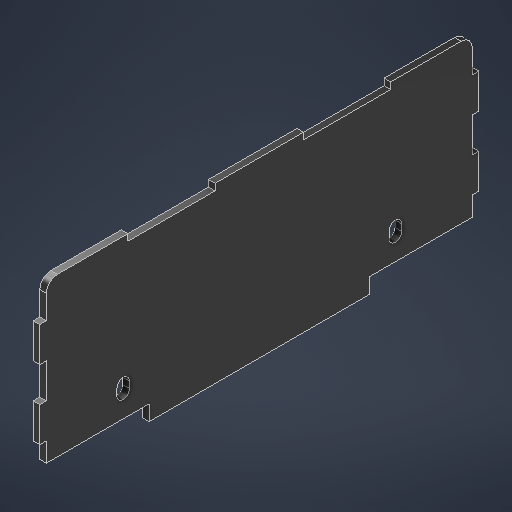
# Autodesk Inventor part: ControlBoxWidthFace
Saved by Autodesk Inventor 2027.1 (Build 311270010, 270A)
## iProperties
Created: 2026-10-13
Part Number: ControlBoxWidthFace
Material: MDF Medium Density Fiberboard
Document SubType Name: Modeling
Designer: SDS Scholar
Density: 0.8 g/cm^3
Appearance: Glossy - Black
Mass: 36.6564 g
Surface Area: 323.47 cm^2
Volume: 45.8205 cm^3
Author: SDS Scholar
Autodesk Inventor part; units mm, degrees
ref_plane "YZ Plane" through (0, 0, 0) normal (1, 0, 0) x (0, 1, 0)
ref_plane "XZ Plane" through (0, 0, 0) normal (0, 1, 0) x (-1, 0, 0)
ref_plane "XY Plane" through (0, 0, 0) normal (0, 0, 1) x (1, 0, 0)
sketch "Sketch1" plane through (0, 0, 0) normal (1, 0, 0) x (0, 1, 0)
  line L0 (39.5, 100) -> (-39.5, 100)
  line L1 (-39.5, 100) -> (-39.5, -100)
  line L2 (-39.5, -100) -> (39.5, -100)
  line L3 (39.5, -100) -> (39.5, 100)
  point P0 (0, 0)
  point P1 (39.5, 0)
  point P2 (0, -100)
  dimension "d0" = 200
  dimension "d1" = 79
  constraints: 8 end point, 2 midpoint, 2 parallel, 1 horizontal, 1 horizontal alignment, 1 perpendicular, 1 vertical alignment
  measures "d0" distance of L2.end L0.start
  measures "d1" distance of L0.start L0.end
extrude "Extrusion1" add sketch "Sketch1" along normal blind 3
sketch "Sketch2" plane through (3, 0, 0) normal (1, 0, 0) x (0, 0, -1)
  line L0 (-100, -39.5) -> (100, -39.5) projected
  line L1 (100, -39.5) -> (100, 39.5) projected
  line L2 (100, 39.5) -> (-100, 39.5) projected
  line L3 (-100, 39.5) -> (-100, -39.5) projected
  line L4 (-97, 36.5) -> (97, 36.5)
  line L5 (97, 36.5) -> (97, -39.5)
  line L6 (-97, -39.5) -> (-97, 36.5)
  line L7 (100, 39.5) -> (-100, 39.5) projected
  line L8 (-100, 39.5) -> (-59.85, 39.5)
  line L9 (-59.85, 39.5) -> (-59.85, 36.5)
  line L10 (-59.85, 36.5) -> (-100, 36.5)
  line L11 (-100, 36.5) -> (-100, 39.5)
  line L12 (-59.85, 39.5) -> (-20.15, 39.5)
  line L13 (-20.15, 39.5) -> (-20.15, 36.5)
  line L14 (-20.15, 36.5) -> (-59.85, 36.5)
  line L15 (-59.85, 36.5) -> (-59.85, 39.5)
  line L16 (-100, 39.5) -> (-100, -39.5) projected
  line L17 (-100, 0) -> (100, 0) construction
  line L18 (0, 39.5) -> (0, -39.5) construction
  line L19 (20.15, 39.5) -> (20.15, 36.5)
  line L20 (59.85, 39.5) -> (59.85, 36.5)
  line L21 (-100, 39.5) -> (-97, 39.5)
  line L22 (-97, 39.5) -> (-97, 23.7)
  line L23 (-97, 23.7) -> (-100, 23.7)
  line L24 (-100, 23.7) -> (-100, 39.5)
  line L25 (-97, 7.9) -> (-100, 7.9)
  line L26 (-97, -7.9) -> (-100, -7.9)
  line L27 (-97, -23.7) -> (-100, -23.7)
  line L28 (97, 23.7) -> (100, 23.7)
  line L29 (97, 7.9) -> (100, 7.9)
  line L30 (97, -7.9) -> (100, -7.9)
  line L31 (97, -23.7) -> (100, -23.7)
  line L32 (97, 36.5) -> (97, 39.5)
  dimension "d51" = 3
  dimension "d52" = 40.15
  dimension "d53" = 39.7
  dimension "d56" = 80
  dimension "d61" = 15.8
  dimension "d64" = 15.8
  dimension "d69" = 3
  dimension "d70" = 76
  dimension "d71" = 76
  constraints: 54 end point, 8 symmetric about line, 7 point on line, 6 parallel, 4 horizontal, 4 midpoint, 3 perpendicular, 1 vertical, 1 vertical alignment, 15 other
  measures "d51" distance between parallel lines of L2 L4
  measures "d52" distance of L9.end L10.end
  measures "d53" distance of L13.end L14.end
  measures "d56" distance of L8.end L19.start
  measures "d61" distance of L21.end L22.end
  measures "d64" distance of L22.end L25.start
  measures "d69" distance of L22.end L23.end
  measures "d70" distance of L6.start L4.start
  measures "d71" distance of L4.end L5.end
extrude "Extrusion2" cut sketch "Sketch2" against normal blind 10 contours L3 L27 L6 L0 | L5 L31 L1 L0 | L3 L25 L6 L26 | L5 L29 L1 L30 | L3 L10 L6 L23 | L3 L2 L22 L10 | L5 L32 L2 L1 L28 | L9 L2 L13 L4 | L4 L19 L2 L20
sketch "Sketch3" plane through (3, 0, 0) normal (1, 0, 0) x (0, 0, -1)
  line L0 (20.15, 39.5) -> (-20.15, 39.5) projected
  line L1 (-100, 23.7) -> (-100, 7.9) projected
  line L2 (-97, -39.5) -> (97, -39.5) projected
  line L3 (100, 7.9) -> (100, 23.7) projected
  line L4 (-97, -32.5) -> (97, -32.5)
  line L5 (-50.15, -32.5) -> (50.15, -32.5)
  line L6 (50.15, -32.5) -> (50.15, -39.5)
  line L7 (50.15, -39.5) -> (-50.15, -39.5)
  line L8 (-50.15, -39.5) -> (-50.15, -32.5)
  line L9 (-97, 23.7) -> (-100, 23.7) projected
  line L10 (-100, 7.9) -> (-97, 7.9) projected
  line L11 (-97, 7.9) -> (-97, -7.9) projected
  line L12 (-97, -7.9) -> (-100, -7.9) projected
  line L13 (-100, -7.9) -> (-100, -23.7) projected
  line L14 (-100, -23.7) -> (-97, -23.7) projected
  line L15 (-97, -23.7) -> (-97, -39.5) projected
  line L16 (97, -39.5) -> (97, -23.7) projected
  line L17 (97, -23.7) -> (100, -23.7) projected
  line L18 (100, -23.7) -> (100, -7.9) projected
  line L19 (100, -7.9) -> (97, -7.9) projected
  line L20 (97, -7.9) -> (97, 7.9) projected
  line L21 (97, 7.9) -> (100, 7.9) projected
  line L22 (100, 23.7) -> (97, 23.7) projected
  line L23 (97, 23.7) -> (97, 39.5) projected
  line L24 (97, 39.5) -> (59.85, 39.5) projected
  line L25 (59.85, 39.5) -> (59.85, 36.5) projected
  line L26 (59.85, 36.5) -> (20.15, 36.5) projected
  line L27 (20.15, 36.5) -> (20.15, 39.5) projected
  line L28 (-20.15, 39.5) -> (-20.15, 36.5) projected
  line L29 (-20.15, 36.5) -> (-59.85, 36.5) projected
  line L30 (-59.85, 36.5) -> (-59.85, 39.5) projected
  line L31 (-59.85, 39.5) -> (-97, 39.5) projected
  line L32 (-97, 39.5) -> (-97, 23.7) projected
  point P0 (0, 0)
  point P1 (0, -39.5)
  point P2 (0, -39.5)
  point P3 (50.15, -32.5)
  point P4 (-50.15, -39.5)
  point P5 (-100, -32.5)
  dimension "d40" = 7
  dimension "d41" = 100.3
  constraints: 10 end point, 4 point on line, 2 midpoint, 2 parallel, 2 perpendicular, 1 coincident, 1 horizontal
  measures "d40" distance between parallel lines of L2 L4
  measures "d41" distance between parallel lines of L6 L8
extrude "Extrusion3" cut sketch "Sketch3" against normal through all contours L16 L2 L6 L4 | L4 L8 L2 L15
sketch "Sketch4" plane through (3, 0, 0) normal (1, 0, 0) x (0, 0, -1)
  line L0 (50.15, -32.5) -> (97, -32.5) projected
  line L1 (100, 7.9) -> (100, 23.7) projected
  line L2 (20.15, 39.5) -> (-20.15, 39.5) projected
  line L3 (-100, 23.7) -> (-100, 7.9) projected
  line L4 (0, -39.5) -> (0, 39.5) construction
  line L5 (-62, -22) -> (-62, -19) construction
  line L6 (-59.1, -22) -> (-59.1, -19)
  line L7 (-64.9, -19) -> (-64.9, -22)
  arc A0 (-64.9, -22) -> (-59.1, -22) centre (-62, -22) ccw
  arc A1 (-59.1, -19) -> (-64.9, -19) centre (-62, -19) ccw
  line L8 (62, -22) -> (62, -19) construction
  line L9 (59.1, -22) -> (59.1, -19)
  line L10 (64.9, -19) -> (64.9, -22)
  arc A2 (59.1, -22) -> (64.9, -22) centre (62, -22) ccw
  arc A3 (64.9, -19) -> (59.1, -19) centre (62, -19) ccw
  line L11 (97, -32.5) -> (97, -23.7) projected
  line L12 (97, -23.7) -> (100, -23.7) projected
  line L13 (100, -23.7) -> (100, -7.9) projected
  line L14 (100, -7.9) -> (97, -7.9) projected
  line L15 (97, -7.9) -> (97, 7.9) projected
  line L16 (97, 7.9) -> (100, 7.9) projected
  line L17 (100, 23.7) -> (97, 23.7) projected
  line L18 (97, 23.7) -> (97, 39.5) projected
  line L19 (97, 39.5) -> (59.85, 39.5) projected
  line L20 (59.85, 39.5) -> (59.85, 36.5) projected
  line L21 (59.85, 36.5) -> (20.15, 36.5) projected
  line L22 (20.15, 36.5) -> (20.15, 39.5) projected
  line L23 (-20.15, 39.5) -> (-20.15, 36.5) projected
  line L24 (-20.15, 36.5) -> (-59.85, 36.5) projected
  line L25 (-59.85, 36.5) -> (-59.85, 39.5) projected
  line L26 (-59.85, 39.5) -> (-97, 39.5) projected
  line L27 (-97, 39.5) -> (-97, 23.7) projected
  line L28 (-97, 23.7) -> (-100, 23.7) projected
  line L29 (-100, 7.9) -> (-97, 7.9) projected
  line L30 (-97, 7.9) -> (-97, -7.9) projected
  line L31 (-97, -7.9) -> (-100, -7.9) projected
  line L32 (-100, -7.9) -> (-100, -23.7) projected
  line L33 (-100, -23.7) -> (-97, -23.7) projected
  line L34 (-97, -23.7) -> (-97, -32.5) projected
  line L35 (-50.15, -32.5) -> (-50.15, -39.5) projected
  line L36 (-50.15, -39.5) -> (50.15, -39.5) projected
  line L37 (50.15, -39.5) -> (50.15, -32.5) projected
  line L38 (-97, -32.5) -> (-50.15, -32.5) projected
  line L39 (-50.15, -39.5) -> (50.15, -39.5) projected
  point P0 (0, 0)
  point P1 (-62, -20.5)
  point P2 (62, -20.5)
  point P3 (0, 0)
  dimension "d44" = 3
  dimension "d45" = 5.8
  dimension "d72" = 10.5
  dimension "d73" = 35
  dimension "d74" = 79
  constraints: 18 end point, 8 point on circle, 7 symmetric about line, 4 centre point, 4 tangent, 2 midpoint, 1 coincident, 1 parallel, 1 perpendicular, 1 vertical, 2 other
  measures "d44" distance of L5.start L5.end
  measures "d45" diameter of A1
  measures "d72" distance from line of L38 L5.start
  measures "d73" distance between parallel lines of L34 L5
  measures "d74" distance of L4.start L4.end
extrude "Extrusion4" cut sketch "Sketch4" against normal blind 10 contours A0 L7 A1 L6 | L9 A3 L10 A2
fillet "Fillet1" [suppressed]
fillet "Fillet2" radius 5 2 edges at (1.5, 39.5, 97) (1.5, 39.5, -97)
equation "\"d0\" = ContolBoxWidth"
equation "\"GridProcutClearance\" = 5"
equation "\"GridBorderThickness\" = 5"
equation "\"GridBorderFillets\" = 7"
equation "\"GridTotalSize\" = 65"
equation "\"GridRobotClearance\" = 65"
equation "\"AluminiumExtrusionClearance\" = 35"
equation "\"BaseTotalLength\" = 885"
equation "\"WorkspaceLength\" = 515"
equation "\"WorkspaceHeight\" = 183"
equation "\"AxesBaseFillet\" = 15"
equation "\"Zaxis\" = 197"
equation "\"ProductTotalHeight\" = 45"
equation "\"VerticalStroke\" = 105"
equation "\"BackArea\" = 165"
equation "\"CylinderStroke\" = 75"
equation "\"BoxesWidth\" = 125"
equation "\"ContolBoxWidth\" = 200"
equation "\"BaseWoodThickness\" = 7"
equation "\"kerf\" = 1.5"
equation "\"Kerf\" = 0.3"
equation "\"RxThickness\" = 1.8"
equation "\"support_2\" = 265"
body "Solid1"
